Autodesk Fusion 360 part; units mm, degrees
(part 2 of 5)
  arc A33 (14.5583, -1.6533) -> (13.4619, -2.4667) centre (14.4455, -2.6469) ccw
  line L16 (14.5583, -1.6533) -> (14.9391, -1.6965)
  spline S16 degree 5 poles (14.9391, -1.6965) (14.9477, -1.6975) (14.9651, -1.6992) (14.9913, -1.7011) (15.0262, -1.7021) (15.07, -1.7014) (15.1138, -1.6994) (15.1577, -1.6964) (15.2016, -1.693) (15.2456, -1.6893) (15.2896, -1.6852) (15.3336, -1.6807) (15.3777, -1.6756) (15.4217, -1.6698) (15.4658, -1.6634) (15.5099, -1.6563) (15.554, -1.6486) (15.5981, -1.6405) (15.6422, -1.632) (15.6863, -1.6231) (15.7304, -1.6138) (15.7745, -1.6041) (15.8186, -1.594) (15.8627, -1.5835) (15.9068, -1.5726) (15.9508, -1.5612) (15.9949, -1.5494) (16.039, -1.5373) (16.083, -1.5248) (16.127, -1.512) (16.171, -1.4988) (16.215, -1.4852) (16.2589, -1.4713) (16.3029, -1.4571) (16.3468, -1.4425) (16.3907, -1.4276) (16.4345, -1.4123) (16.4784, -1.3967) (16.5222, -1.3808) (16.5659, -1.3646) (16.6097, -1.348) (16.6534, -1.3312) (16.6971, -1.314) (16.7407, -1.2965) (16.7844, -1.2787) (16.8279, -1.2606) (16.8715, -1.2422) (16.915, -1.2235) (16.9585, -1.2045) (17.0019, -1.1853) (17.0453, -1.1657) (17.0886, -1.1458) (17.1319, -1.1257) (17.1752, -1.1053) (17.2184, -1.0846) (17.2616, -1.0636) (17.3047, -1.0423) (17.3478, -1.0208) (17.3908, -0.9989) (17.4338, -0.9769) (17.4767, -0.9545) (17.5196, -0.9319) (17.5624, -0.909) (17.6052, -0.8858) (17.6479, -0.8624) (17.6906, -0.8387) (17.7332, -0.8147) (17.7758, -0.7905) (17.8183, -0.766) (17.8607, -0.7413) (17.9031, -0.7163) (17.937, -0.6962) (17.9623, -0.6809) (17.9792, -0.6707) (17.9877, -0.6655) knots 0 0 0 0 0 0 0.01428571 0.02857143 0.04285714 0.05714286 0.07142857 0.08571429 0.1 0.11428571 0.12857143 0.14285714 0.15714286 0.17142857 0.18571429 0.2 0.21428571 0.22857143 0.24285714 0.25714286 0.27142857 0.28571429 0.3 0.31428571 0.32857143 0.34285714 0.35714286 0.37142857 0.38571429 0.4 0.41428571 0.42857143 0.44285714 0.45714286 0.47142857 0.48571429 0.5 0.51428571 0.52857143 0.54285714 0.55714286 0.57142857 0.58571429 0.6 0.61428571 0.62857143 0.64285714 0.65714286 0.67142857 0.68571429 0.7 0.71428571 0.72857143 0.74285714 0.75714286 0.77142857 0.78571429 0.8 0.81428571 0.82857143 0.84285714 0.85714286 0.87142857 0.88571429 0.9 0.91428571 0.92857143 0.94285714 0.95714286 0.97142857 0.98571429 1 1 1 1 1 1
  arc A34 (17.9877, -0.6655) -> (17.9877, 0.6655) centre (0, 0) ccw
  spline S17 degree 5 poles (17.9877, 0.6655) (17.9792, 0.6707) (17.9623, 0.6809) (17.937, 0.6962) (17.9031, 0.7163) (17.8607, 0.7413) (17.8183, 0.766) (17.7758, 0.7905) (17.7332, 0.8147) (17.6906, 0.8387) (17.6479, 0.8624) (17.6052, 0.8858) (17.5624, 0.909) (17.5196, 0.9319) (17.4767, 0.9545) (17.4338, 0.9769) (17.3908, 0.9989) (17.3478, 1.0208) (17.3047, 1.0423) (17.2616, 1.0636) (17.2184, 1.0846) (17.1752, 1.1053) (17.1319, 1.1257) (17.0886, 1.1458) (17.0453, 1.1657) (17.0019, 1.1853) (16.9585, 1.2045) (16.915, 1.2235) (16.8715, 1.2422) (16.8279, 1.2606) (16.7844, 1.2787) (16.7407, 1.2965) (16.6971, 1.314) (16.6534, 1.3312) (16.6097, 1.348) (16.5659, 1.3646) (16.5222, 1.3808) (16.4784, 1.3967) (16.4345, 1.4123) (16.3907, 1.4276) (16.3468, 1.4425) (16.3029, 1.4571) (16.2589, 1.4713) (16.215, 1.4852) (16.171, 1.4988) (16.127, 1.512) (16.083, 1.5248) (16.039, 1.5373) (15.9949, 1.5494) (15.9508, 1.5612) (15.9068, 1.5726) (15.8627, 1.5835) (15.8186, 1.594) (15.7745, 1.6041) (15.7304, 1.6138) (15.6863, 1.6231) (15.6422, 1.632) (15.5981, 1.6405) (15.554, 1.6486) (15.5099, 1.6563) (15.4658, 1.6634) (15.4217, 1.6698) (15.3777, 1.6756) (15.3336, 1.6807) (15.2896, 1.6852) (15.2456, 1.6893) (15.2016, 1.693) (15.1577, 1.6964) (15.1138, 1.6994) (15.07, 1.7014) (15.0262, 1.7021) (14.9913, 1.7011) (14.9651, 1.6992) (14.9477, 1.6975) (14.9391, 1.6965) knots -1 -1 -1 -1 -1 -1 -0.98571429 -0.97142857 -0.95714286 -0.94285714 -0.92857143 -0.91428571 -0.9 -0.88571429 -0.87142857 -0.85714286 -0.84285714 -0.82857143 -0.81428571 -0.8 -0.78571429 -0.77142857 -0.75714286 -0.74285714 -0.72857143 -0.71428571 -0.7 -0.68571429 -0.67142857 -0.65714286 -0.64285714 -0.62857143 -0.61428571 -0.6 -0.58571429 -0.57142857 -0.55714286 -0.54285714 -0.52857143 -0.51428571 -0.5 -0.48571429 -0.47142857 -0.45714286 -0.44285714 -0.42857143 -0.41428571 -0.4 -0.38571429 -0.37142857 -0.35714286 -0.34285714 -0.32857143 -0.31428571 -0.3 -0.28571429 -0.27142857 -0.25714286 -0.24285714 -0.22857143 -0.21428571 -0.2 -0.18571429 -0.17142857 -0.15714286 -0.14285714 -0.12857143 -0.11428571 -0.1 -0.08571429 -0.07142857 -0.05714286 -0.04285714 -0.02857143 -0.01428571 0 0 0 0 0 0
  line L17 (14.9391, 1.6965) -> (14.5583, 1.6533)
  arc A35 (13.4619, 2.4667) -> (14.5583, 1.6533) centre (14.4455, 2.6469) ccw
  arc A36 (13.4619, 2.4667) -> (13.3811, 2.8727) centre (0, 0) ccw
  arc A37 (14.0828, 4.0438) -> (13.3811, 2.8727) centre (14.3588, 3.0826) ccw
  line L18 (14.0828, 4.0438) -> (14.4511, 4.1495)
  spline S18 degree 5 poles (14.4511, 4.1495) (14.4595, 4.152) (14.4763, 4.157) (14.5011, 4.1653) (14.5338, 4.1777) (14.5739, 4.1951) (14.6136, 4.2138) (14.6531, 4.2333) (14.6924, 4.2533) (14.7316, 4.2735) (14.7707, 4.2941) (14.8096, 4.3152) (14.8483, 4.3367) (14.8868, 4.3589) (14.9251, 4.3818) (14.9631, 4.4052) (15.0009, 4.4291) (15.0385, 4.4535) (15.076, 4.4783) (15.1134, 4.5034) (15.1506, 4.5288) (15.1876, 4.5546) (15.2245, 4.5808) (15.2612, 4.6074) (15.2977, 4.6344) (15.3341, 4.6618) (15.3703, 4.6895) (15.4064, 4.7176) (15.4423, 4.746) (15.478, 4.7747) (15.5136, 4.8037) (15.549, 4.833) (15.5843, 4.8627) (15.6195, 4.8927) (15.6545, 4.9229) (15.6893, 4.9535) (15.724, 4.9844) (15.7585, 5.0156) (15.7929, 5.0471) (15.8271, 5.0788) (15.8612, 5.1108) (15.8952, 5.1432) (15.9289, 5.1757) (15.9626, 5.2086) (15.9961, 5.2417) (16.0294, 5.2751) (16.0626, 5.3088) (16.0956, 5.3427) (16.1285, 5.3769) (16.1613, 5.4113) (16.1939, 5.446) (16.2263, 5.4809) (16.2586, 5.5161) (16.2908, 5.5515) (16.3228, 5.5872) (16.3546, 5.6231) (16.3863, 5.6593) (16.4179, 5.6957) (16.4493, 5.7323) (16.4806, 5.7691) (16.5117, 5.8062) (16.5426, 5.8435) (16.5734, 5.8811) (16.6041, 5.9189) (16.6346, 5.9569) (16.6649, 5.9951) (16.6951, 6.0335) (16.7252, 6.0722) (16.7551, 6.111) (16.7849, 6.1501) (16.8144, 6.1894) (16.838, 6.221) (16.8556, 6.2448) (16.8673, 6.2607) (16.8732, 6.2687) knots 0 0 0 0 0 0 0.01428571 0.02857143 0.04285714 0.05714286 0.07142857 0.08571429 0.1 0.11428571 0.12857143 0.14285714 0.15714286 0.17142857 0.18571429 0.2 0.21428571 0.22857143 0.24285714 0.25714286 0.27142857 0.28571429 0.3 0.31428571 0.32857143 0.34285714 0.35714286 0.37142857 0.38571429 0.4 0.41428571 0.42857143 0.44285714 0.45714286 0.47142857 0.48571429 0.5 0.51428571 0.52857143 0.54285714 0.55714286 0.57142857 0.58571429 0.6 0.61428571 0.62857143 0.64285714 0.65714286 0.67142857 0.68571429 0.7 0.71428571 0.72857143 0.74285714 0.75714286 0.77142857 0.78571429 0.8 0.81428571 0.82857143 0.84285714 0.85714286 0.87142857 0.88571429 0.9 0.91428571 0.92857143 0.94285714 0.95714286 0.97142857 0.98571429 1 1 1 1 1 1
  arc A38 (16.8732, 6.2687) -> (16.3638, 7.4985) centre (0, 0) ccw
  spline S19 degree 5 poles (16.3638, 7.4985) (16.354, 7.5) (16.3345, 7.503) (16.3052, 7.5073) (16.2662, 7.513) (16.2175, 7.5199) (16.1688, 7.5265) (16.1202, 7.5328) (16.0716, 7.5389) (16.023, 7.5447) (15.9746, 7.5503) (15.9261, 7.5556) (15.8777, 7.5606) (15.8294, 7.5654) (15.7811, 7.5699) (15.7329, 7.5741) (15.6847, 7.5781) (15.6366, 7.5818) (15.5886, 7.5852) (15.5406, 7.5883) (15.4927, 7.5912) (15.4448, 7.5938) (15.3971, 7.5961) (15.3493, 7.5982) (15.3017, 7.5999) (15.2541, 7.6014) (15.2066, 7.6026) (15.1592, 7.6035) (15.1118, 7.6041) (15.0646, 7.6044) (15.0174, 7.6045) (14.9703, 7.6042) (14.9233, 7.6037) (14.8763, 7.6028) (14.8295, 7.6017) (14.7827, 7.6002) (14.7361, 7.5984) (14.6895, 7.5964) (14.6431, 7.594) (14.5967, 7.5913) (14.5504, 7.5883) (14.5043, 7.585) (14.4582, 7.5813) (14.4123, 7.5774) (14.3665, 7.573) (14.3208, 7.5684) (14.2752, 7.5634) (14.2298, 7.5581) (14.1844, 7.5525) (14.1392, 7.5465) (14.0942, 7.5401) (14.0492, 7.5334) (14.0045, 7.5262) (13.9599, 7.5187) (13.9154, 7.5107) (13.8711, 7.5024) (13.827, 7.4938) (13.783, 7.4847) (13.7391, 7.4754) (13.6955, 7.4656) (13.652, 7.4552) (13.6088, 7.4444) (13.5659, 7.4328) (13.5232, 7.4207) (13.4809, 7.408) (13.4387, 7.3949) (13.3966, 7.3816) (13.3547, 7.3679) (13.313, 7.3538) (13.2717, 7.3389) (13.231, 7.3228) (13.1992, 7.3085) (13.1757, 7.2968) (13.1603, 7.2886) (13.1527, 7.2843) knots -1 -1 -1 -1 -1 -1 -0.98571429 -0.97142857 -0.95714286 -0.94285714 -0.92857143 -0.91428571 -0.9 -0.88571429 -0.87142857 -0.85714286 -0.84285714 -0.82857143 -0.81428571 -0.8 -0.78571429 -0.77142857 -0.75714286 -0.74285714 -0.72857143 -0.71428571 -0.7 -0.68571429 -0.67142857 -0.65714286 -0.64285714 -0.62857143 -0.61428571 -0.6 -0.58571429 -0.57142857 -0.55714286 -0.54285714 -0.52857143 -0.51428571 -0.5 -0.48571429 -0.47142857 -0.45714286 -0.44285714 -0.42857143 -0.41428571 -0.4 -0.38571429 -0.37142857 -0.35714286 -0.34285714 -0.32857143 -0.31428571 -0.3 -0.28571429 -0.27142857 -0.25714286 -0.24285714 -0.22857143 -0.21428571 -0.2 -0.18571429 -0.17142857 -0.15714286 -0.14285714 -0.12857143 -0.11428571 -0.1 -0.08571429 -0.07142857 -0.05714286 -0.04285714 -0.02857143 -0.01428571 0 0 0 0 0 0
  line L19 (13.1527, 7.2843) -> (12.8175, 7.0987)
  arc A39 (11.4932, 7.4305) -> (12.8175, 7.0987) centre (12.333, 7.9735) ccw
  arc A40 (11.4932, 7.4305) -> (11.2632, 7.7748) centre (0, 0) ccw
  arc A41 (11.4634, 9.1252) -> (11.2632, 7.7748) centre (12.0862, 8.3429) ccw
  line L20 (11.4634, 9.1252) -> (11.7631, 9.3639)
  spline S20 degree 5 poles (11.7631, 9.3639) (11.77, 9.3693) (11.7835, 9.3804) (11.8033, 9.3976) (11.8287, 9.4216) (11.8592, 9.453) (11.8887, 9.4854) (11.9177, 9.5186) (11.9463, 9.552) (11.9748, 9.5858) (12.003, 9.6198) (12.031, 9.6541) (12.0585, 9.6888) (12.0856, 9.7241) (12.1121, 9.7598) (12.1383, 9.796) (12.1641, 9.8326) (12.1895, 9.8695) (12.2147, 9.9067) (12.2396, 9.9442) (12.2642, 9.982) (12.2886, 10.02) (12.3126, 10.0583) (12.3363, 10.0969) (12.3598, 10.1358) (12.3829, 10.175) (12.4057, 10.2145) (12.4283, 10.2542) (12.4506, 10.2942) (12.4726, 10.3344) (12.4944, 10.3748) (12.5159, 10.4155) (12.5372, 10.4564) (12.5582, 10.4975) (12.5789, 10.5389) (12.5994, 10.5805) (12.6196, 10.6223) (12.6396, 10.6643) (12.6593, 10.7066) (12.6788, 10.749) (12.698, 10.7916) (12.717, 10.8345) (12.7358, 10.8775) (12.7543, 10.9207) (12.7725, 10.9642) (12.7905, 11.0078) (12.8083, 11.0516) (12.8259, 11.0955) (12.8432, 11.1397) (12.8603, 11.184) (12.8771, 11.2286) (12.8937, 11.2733) (12.9101, 11.3181) (12.9262, 11.3632) (12.9422, 11.4084) (12.9578, 11.4537) (12.9733, 11.4993) (12.9885, 11.545) (13.0035, 11.5908) (13.0183, 11.6368) (13.0328, 11.683) (13.0472, 11.7293) (13.0613, 11.7758) (13.0751, 11.8224) (13.0888, 11.8692) (13.1022, 11.9161) (13.1154, 11.9632) (13.1284, 12.0104) (13.1411, 12.0578) (13.1536, 12.1052) (13.1659, 12.1529) (13.1756, 12.1911) (13.1828, 12.2198) (13.1875, 12.239) (13.1898, 12.2486) knots 0 0 0 0 0 0 0.01428571 0.02857143 0.04285714 0.05714286 0.07142857 0.08571429 0.1 0.11428571 0.12857143 0.14285714 0.15714286 0.17142857 0.18571429 0.2 0.21428571 0.22857143 0.24285714 0.25714286 0.27142857 0.28571429 0.3 0.31428571 0.32857143 0.34285714 0.35714286 0.37142857 0.38571429 0.4 0.41428571 0.42857143 0.44285714 0.45714286 0.47142857 0.48571429 0.5 0.51428571 0.52857143 0.54285714 0.55714286 0.57142857 0.58571429 0.6 0.61428571 0.62857143 0.64285714 0.65714286 0.67142857 0.68571429 0.7 0.71428571 0.72857143 0.74285714 0.75714286 0.77142857 0.78571429 0.8 0.81428571 0.82857143 0.84285714 0.85714286 0.87142857 0.88571429 0.9 0.91428571 0.92857143 0.94285714 0.95714286 0.97142857 0.98571429 1 1 1 1 1 1
  arc A42 (13.1898, 12.2486) -> (12.2486, 13.1898) centre (0, 0) ccw
  spline S21 degree 5 poles (12.2486, 13.1898) (12.239, 13.1875) (12.2198, 13.1828) (12.1911, 13.1756) (12.1529, 13.1659) (12.1052, 13.1536) (12.0578, 13.1411) (12.0104, 13.1284) (11.9632, 13.1154) (11.9161, 13.1022) (11.8692, 13.0888) (11.8224, 13.0751) (11.7758, 13.0613) (11.7293, 13.0472) (11.683, 13.0328) (11.6368, 13.0183) (11.5908, 13.0035) (11.545, 12.9885) (11.4993, 12.9733) (11.4537, 12.9578) (11.4084, 12.9422) (11.3632, 12.9262) (11.3181, 12.9101) (11.2733, 12.8937) (11.2286, 12.8771) (11.184, 12.8603) (11.1397, 12.8432) (11.0955, 12.8259) (11.0516, 12.8083) (11.0078, 12.7905) (10.9642, 12.7725) (10.9207, 12.7543) (10.8775, 12.7358) (10.8345, 12.717) (10.7916, 12.698) (10.749, 12.6788) (10.7066, 12.6593) (10.6643, 12.6396) (10.6223, 12.6196) (10.5805, 12.5994) (10.5389, 12.5789) (10.4975, 12.5582) (10.4564, 12.5372) (10.4155, 12.5159) (10.3748, 12.4944) (10.3344, 12.4726) (10.2942, 12.4506) (10.2542, 12.4283) (10.2145, 12.4057) (10.175, 12.3829) (10.1358, 12.3598) (10.0969, 12.3363) (10.0583, 12.3126) (10.02, 12.2886) (9.982, 12.2642) (9.9442, 12.2396) (9.9067, 12.2147) (9.8695, 12.1895) (9.8326, 12.1641) (9.796, 12.1383) (9.7598, 12.1121) (9.7241, 12.0856) (9.6888, 12.0585) (9.6541, 12.031) (9.6198, 12.003) (9.5858, 11.9748) (9.552, 11.9463) (9.5186, 11.9177) (9.4854, 11.8887) (9.453, 11.8592) (9.4216, 11.8287) (9.3976, 11.8033) (9.3804, 11.7835) (9.3693, 11.77) (9.3639, 11.7631) knots -1 -1 -1 -1 -1 -1 -0.98571429 -0.97142857 -0.95714286 -0.94285714 -0.92857143 -0.91428571 -0.9 -0.88571429 -0.87142857 -0.85714286 -0.84285714 -0.82857143 -0.81428571 -0.8 -0.78571429 -0.77142857 -0.75714286 -0.74285714 -0.72857143 -0.71428571 -0.7 -0.68571429 -0.67142857 -0.65714286 -0.64285714 -0.62857143 -0.61428571 -0.6 -0.58571429 -0.57142857 -0.55714286 -0.54285714 -0.52857143 -0.51428571 -0.5 -0.48571429 -0.47142857 -0.45714286 -0.44285714 -0.42857143 -0.41428571 -0.4 -0.38571429 -0.37142857 -0.35714286 -0.34285714 -0.32857143 -0.31428571 -0.3 -0.28571429 -0.27142857 -0.25714286 -0.24285714 -0.22857143 -0.21428571 -0.2 -0.18571429 -0.17142857 -0.15714286 -0.14285714 -0.12857143 -0.11428571 -0.1 -0.08571429 -0.07142857 -0.05714286 -0.04285714 -0.02857143 -0.01428571 0 0 0 0 0 0
  line L21 (9.3639, 11.7631) -> (9.1252, 11.4634)
  arc A43 (7.7748, 11.2632) -> (9.1252, 11.4634) centre (8.3429, 12.0862) ccw
  arc A44 (7.7748, 11.2632) -> (7.4305, 11.4932) centre (0, 0) ccw
  arc A45 (7.0987, 12.8175) -> (7.4305, 11.4932) centre (7.9735, 12.333) ccw
  line L22 (7.0987, 12.8175) -> (7.2843, 13.1527)
  spline S22 degree 5 poles (7.2843, 13.1527) (7.2886, 13.1603) (7.2968, 13.1757) (7.3085, 13.1992) (7.3228, 13.231) (7.3389, 13.2717) (7.3538, 13.313) (7.3679, 13.3547) (7.3816, 13.3966) (7.3949, 13.4387) (7.408, 13.4809) (7.4207, 13.5232) (7.4328, 13.5659) (7.4444, 13.6088) (7.4552, 13.652) (7.4656, 13.6955) (7.4754, 13.7391) (7.4847, 13.783) (7.4938, 13.827) (7.5024, 13.8711) (7.5107, 13.9154) (7.5187, 13.9599) (7.5262, 14.0045) (7.5334, 14.0492) (7.5401, 14.0942) (7.5465, 14.1392) (7.5525, 14.1844) (7.5581, 14.2298) (7.5634, 14.2752) (7.5684, 14.3208) (7.573, 14.3665) (7.5774, 14.4123) (7.5813, 14.4582) (7.585, 14.5043) (7.5883, 14.5504) (7.5913, 14.5967) (7.594, 14.6431) (7.5964, 14.6895) (7.5984, 14.7361) (7.6002, 14.7827) (7.6017, 14.8295) (7.6028, 14.8763) (7.6037, 14.9233) (7.6042, 14.9703) (7.6045, 15.0174) (7.6044, 15.0646) (7.6041, 15.1118) (7.6035, 15.1592) (7.6026, 15.2066) (7.6014, 15.2541) (7.5999, 15.3017) (7.5982, 15.3493) (7.5961, 15.3971) (7.5938, 15.4448) (7.5912, 15.4927) (7.5883, 15.5406) (7.5852, 15.5886) (7.5818, 15.6366) (7.5781, 15.6847) (7.5741, 15.7329) (7.5699, 15.7811) (7.5654, 15.8294) (7.5606, 15.8777) (7.5556, 15.9261) (7.5503, 15.9746) (7.5447, 16.023) (7.5389, 16.0716) (7.5328, 16.1202) (7.5265, 16.1688) (7.5199, 16.2175) (7.513, 16.2662) (7.5073, 16.3052) (7.503, 16.3345) (7.5, 16.354) (7.4985, 16.3638) knots 0 0 0 0 0 0 0.01428571 0.02857143 0.04285714 0.05714286 0.07142857 0.08571429 0.1 0.11428571 0.12857143 0.14285714 0.15714286 0.17142857 0.18571429 0.2 0.21428571 0.22857143 0.24285714 0.25714286 0.27142857 0.28571429 0.3 0.31428571 0.32857143 0.34285714 0.35714286 0.37142857 0.38571429 0.4 0.41428571 0.42857143 0.44285714 0.45714286 0.47142857 0.48571429 0.5 0.51428571 0.52857143 0.54285714 0.55714286 0.57142857 0.58571429 0.6 0.61428571 0.62857143 0.64285714 0.65714286 0.67142857 0.68571429 0.7 0.71428571 0.72857143 0.74285714 0.75714286 0.77142857 0.78571429 0.8 0.81428571 0.82857143 0.84285714 0.85714286 0.87142857 0.88571429 0.9 0.91428571 0.92857143 0.94285714 0.95714286 0.97142857 0.98571429 1 1 1 1 1 1
  arc A46 (7.4985, 16.3638) -> (6.2687, 16.8732) centre (0, 0) ccw
  spline S23 degree 5 poles (6.2687, 16.8732) (6.2607, 16.8673) (6.2448, 16.8556) (6.221, 16.838) (6.1894, 16.8144) (6.1501, 16.7849) (6.111, 16.7551) (6.0722, 16.7252) (6.0335, 16.6951) (5.9951, 16.6649) (5.9569, 16.6346) (5.9189, 16.6041) (5.8811, 16.5734) (5.8435, 16.5426) (5.8062, 16.5117) (5.7691, 16.4806) (5.7323, 16.4493) (5.6957, 16.4179) (5.6593, 16.3863) (5.6231, 16.3546) (5.5872, 16.3228) (5.5515, 16.2908) (5.5161, 16.2586) (5.4809, 16.2263) (5.446, 16.1939) (5.4113, 16.1613) (5.3769, 16.1285) (5.3427, 16.0956) (5.3088, 16.0626) (5.2751, 16.0294) (5.2417, 15.9961) (5.2086, 15.9626) (5.1757, 15.9289) (5.1432, 15.8952) (5.1108, 15.8612) (5.0788, 15.8271) (5.0471, 15.7929) (5.0156, 15.7585) (4.9844, 15.724) (4.9535, 15.6893) (4.9229, 15.6545) (4.8927, 15.6195) (4.8627, 15.5843) (4.833, 15.549) (4.8037, 15.5136) (4.7747, 15.478) (4.746, 15.4423) (4.7176, 15.4064) (4.6895, 15.3703) (4.6618, 15.3341) (4.6344, 15.2977) (4.6074, 15.2612) (4.5808, 15.2245) (4.5546, 15.1876) (4.5288, 15.1506) (4.5034, 15.1134) (4.4783, 15.076) (4.4535, 15.0385) (4.4291, 15.0009) (4.4052, 14.9631) (4.3818, 14.9251) (4.3589, 14.8868) (4.3367, 14.8483) (4.3152, 14.8096) (4.2941, 14.7707) (4.2735, 14.7316) (4.2533, 14.6924) (4.2333, 14.6531) (4.2138, 14.6136) (4.1951, 14.5739) (4.1777, 14.5338) (4.1653, 14.5011) (4.157, 14.4763) (4.152, 14.4595) (4.1495, 14.4511) knots -1 -1 -1 -1 -1 -1 -0.98571429 -0.97142857 -0.95714286 -0.94285714 -0.92857143 -0.91428571 -0.9 -0.88571429 -0.87142857 -0.85714286 -0.84285714 -0.82857143 -0.81428571 -0.8 -0.78571429 -0.77142857 -0.75714286 -0.74285714 -0.72857143 -0.71428571 -0.7 -0.68571429 -0.67142857 -0.65714286 -0.64285714 -0.62857143 -0.61428571 -0.6 -0.58571429 -0.57142857 -0.55714286 -0.54285714 -0.52857143 -0.51428571 -0.5 -0.48571429 -0.47142857 -0.45714286 -0.44285714 -0.42857143 -0.41428571 -0.4 -0.38571429 -0.37142857 -0.35714286 -0.34285714 -0.32857143 -0.31428571 -0.3 -0.28571429 -0.27142857 -0.25714286 -0.24285714 -0.22857143 -0.21428571 -0.2 -0.18571429 -0.17142857 -0.15714286 -0.14285714 -0.12857143 -0.11428571 -0.1 -0.08571429 -0.07142857 -0.05714286 -0.04285714 -0.02857143 -0.01428571 0 0 0 0 0 0
  line L23 (4.1495, 14.4511) -> (4.0438, 14.0828)
  arc A47 (2.8727, 13.3811) -> (4.0438, 14.0828) centre (3.0826, 14.3588) ccw
  arc A48 (2.8727, 13.3811) -> (2.4667, 13.4619) centre (0, 0) ccw
  arc A49 (1.6533, 14.5583) -> (2.4667, 13.4619) centre (2.6469, 14.4455) ccw
  line L24 (1.6533, 14.5583) -> (1.6965, 14.9391)
  spline S24 degree 5 poles (1.6965, 14.9391) (1.6975, 14.9477) (1.6992, 14.9651) (1.7011, 14.9913) (1.7021, 15.0262) (1.7014, 15.07) (1.6994, 15.1138) (1.6964, 15.1577) (1.693, 15.2016) (1.6893, 15.2456) (1.6852, 15.2896) (1.6807, 15.3336) (1.6756, 15.3777) (1.6698, 15.4217) (1.6634, 15.4658) (1.6563, 15.5099) (1.6486, 15.554) (1.6405, 15.5981) (1.632, 15.6422) (1.6231, 15.6863) (1.6138, 15.7304) (1.6041, 15.7745) (1.594, 15.8186) (1.5835, 15.8627) (1.5726, 15.9068) (1.5612, 15.9508) (1.5494, 15.9949) (1.5373, 16.039) (1.5248, 16.083) (1.512, 16.127) (1.4988, 16.171) (1.4852, 16.215) (1.4713, 16.2589) (1.4571, 16.3029) (1.4425, 16.3468) (1.4276, 16.3907) (1.4123, 16.4345) (1.3967, 16.4784) (1.3808, 16.5222) (1.3646, 16.5659) (1.348, 16.6097) (1.3312, 16.6534) (1.314, 16.6971) (1.2965, 16.7407) (1.2787, 16.7844) (1.2606, 16.8279) (1.2422, 16.8715) (1.2235, 16.915) (1.2045, 16.9585) (1.1853, 17.0019) (1.1657, 17.0453) (1.1458, 17.0886) (1.1257, 17.1319) (1.1053, 17.1752) (1.0846, 17.2184) (1.0636, 17.2616) (1.0423, 17.3047) (1.0208, 17.3478) (0.9989, 17.3908) (0.9769, 17.4338) (0.9545, 17.4767) (0.9319, 17.5196) (0.909, 17.5624) (0.8858, 17.6052) (0.8624, 17.6479) (0.8387, 17.6906) (0.8147, 17.7332) (0.7905, 17.7758) (0.766, 17.8183) (0.7413, 17.8607) (0.7163, 17.9031) (0.6962, 17.937) (0.6809, 17.9623) (0.6707, 17.9792) (0.6655, 17.9877) knots 0 0 0 0 0 0 0.01428571 0.02857143 0.04285714 0.05714286 0.07142857 0.08571429 0.1 0.11428571 0.12857143 0.14285714 0.15714286 0.17142857 0.18571429 0.2 0.21428571 0.22857143 0.24285714 0.25714286 0.27142857 0.28571429 0.3 0.31428571 0.32857143 0.34285714 0.35714286 0.37142857 0.38571429 0.4 0.41428571 0.42857143 0.44285714 0.45714286 0.47142857 0.48571429 0.5 0.51428571 0.52857143 0.54285714 0.55714286 0.57142857 0.58571429 0.6 0.61428571 0.62857143 0.64285714 0.65714286 0.67142857 0.68571429 0.7 0.71428571 0.72857143 0.74285714 0.75714286 0.77142857 0.78571429 0.8 0.81428571 0.82857143 0.84285714 0.85714286 0.87142857 0.88571429 0.9 0.91428571 0.92857143 0.94285714 0.95714286 0.97142857 0.98571429 1 1 1 1 1 1
  arc A50 (0.6655, 17.9877) -> (-0.6655, 17.9877) centre (0, 0) ccw
  spline S25 degree 5 poles (-0.6655, 17.9877) (-0.6707, 17.9792) (-0.6809, 17.9623) (-0.6962, 17.937) (-0.7163, 17.9031) (-0.7413, 17.8607) (-0.766, 17.8183) (-0.7905, 17.7758) (-0.8147, 17.7332) (-0.8387, 17.6906) (-0.8624, 17.6479) (-0.8858, 17.6052) (-0.909, 17.5624) (-0.9319, 17.5196) (-0.9545, 17.4767) (-0.9769, 17.4338) (-0.9989, 17.3908) (-1.0208, 17.3478) (-1.0423, 17.3047) (-1.0636, 17.2616) (-1.0846, 17.2184) (-1.1053, 17.1752) (-1.1257, 17.1319) (-1.1458, 17.0886) (-1.1657, 17.0453) (-1.1853, 17.0019) (-1.2045, 16.9585) (-1.2235, 16.915) (-1.2422, 16.8715) (-1.2606, 16.8279) (-1.2787, 16.7844) (-1.2965, 16.7407) (-1.314, 16.6971) (-1.3312, 16.6534) (-1.348, 16.6097) (-1.3646, 16.5659) (-1.3808, 16.5222) (-1.3967, 16.4784) (-1.4123, 16.4345) (-1.4276, 16.3907) (-1.4425, 16.3468) (-1.4571, 16.3029) (-1.4713, 16.2589) (-1.4852, 16.215) (-1.4988, 16.171) (-1.512, 16.127) (-1.5248, 16.083) (-1.5373, 16.039) (-1.5494, 15.9949) (-1.5612, 15.9508) (-1.5726, 15.9068) (-1.5835, 15.8627) (-1.594, 15.8186) (-1.6041, 15.7745) (-1.6138, 15.7304) (-1.6231, 15.6863) (-1.632, 15.6422) (-1.6405, 15.5981) (-1.6486, 15.554) (-1.6563, 15.5099) (-1.6634, 15.4658) (-1.6698, 15.4217) (-1.6756, 15.3777) (-1.6807, 15.3336) (-1.6852, 15.2896) (-1.6893, 15.2456) (-1.693, 15.2016) (-1.6964, 15.1577) (-1.6994, 15.1138) (-1.7014, 15.07) (-1.7021, 15.0262) (-1.7011, 14.9913) (-1.6992, 14.9651) (-1.6975, 14.9477) (-1.6965, 14.9391) knots -1 -1 -1 -1 -1 -1 -0.98571429 -0.97142857 -0.95714286 -0.94285714 -0.92857143 -0.91428571 -0.9 -0.88571429 -0.87142857 -0.85714286 -0.84285714 -0.82857143 -0.81428571 -0.8 -0.78571429 -0.77142857 -0.75714286 -0.74285714 -0.72857143 -0.71428571 -0.7 -0.68571429 -0.67142857 -0.65714286 -0.64285714 -0.62857143 -0.61428571 -0.6 -0.58571429 -0.57142857 -0.55714286 -0.54285714 -0.52857143 -0.51428571 -0.5 -0.48571429 -0.47142857 -0.45714286 -0.44285714 -0.42857143 -0.41428571 -0.4 -0.38571429 -0.37142857 -0.35714286 -0.34285714 -0.32857143 -0.31428571 -0.3 -0.28571429 -0.27142857 -0.25714286 -0.24285714 -0.22857143 -0.21428571 -0.2 -0.18571429 -0.17142857 -0.15714286 -0.14285714 -0.12857143 -0.11428571 -0.1 -0.08571429 -0.07142857 -0.05714286 -0.04285714 -0.02857143 -0.01428571 0 0 0 0 0 0
  line L25 (-1.6965, 14.9391) -> (-1.6533, 14.5583)
  arc A51 (-2.4667, 13.4619) -> (-1.6533, 14.5583) centre (-2.6469, 14.4455) ccw
  arc A52 (-2.4667, 13.4619) -> (-2.8727, 13.3811) centre (0, 0) ccw
  arc A53 (-4.0438, 14.0828) -> (-2.8727, 13.3811) centre (-3.0826, 14.3588) ccw
  line L26 (-4.0438, 14.0828) -> (-4.1495, 14.4511)
  spline S26 degree 5 poles (-4.1495, 14.4511) (-4.152, 14.4595) (-4.157, 14.4763) (-4.1653, 14.5011) (-4.1777, 14.5338) (-4.1951, 14.5739) (-4.2138, 14.6136) (-4.2333, 14.6531) (-4.2533, 14.6924) (-4.2735, 14.7316) (-4.2941, 14.7707) (-4.3152, 14.8096) (-4.3367, 14.8483) (-4.3589, 14.8868) (-4.3818, 14.9251) (-4.4052, 14.9631) (-4.4291, 15.0009) (-4.4535, 15.0385) (-4.4783, 15.076) (-4.5034, 15.1134) (-4.5288, 15.1506) (-4.5546, 15.1876) (-4.5808, 15.2245) (-4.6074, 15.2612) (-4.6344, 15.2977) (-4.6618, 15.3341) (-4.6895, 15.3703) (-4.7176, 15.4064) (-4.746, 15.4423) (-4.7747, 15.478) (-4.8037, 15.5136) (-4.833, 15.549) (-4.8627, 15.5843) (-4.8927, 15.6195) (-4.9229, 15.6545) (-4.9535, 15.6893) (-4.9844, 15.724) (-5.0156, 15.7585) (-5.0471, 15.7929) (-5.0788, 15.8271) (-5.1108, 15.8612) (-5.1432, 15.8952) (-5.1757, 15.9289) (-5.2086, 15.9626) (-5.2417, 15.9961) (-5.2751, 16.0294) (-5.3088, 16.0626) (-5.3427, 16.0956) (-5.3769, 16.1285) (-5.4113, 16.1613) (-5.446, 16.1939) (-5.4809, 16.2263) (-5.5161, 16.2586) (-5.5515, 16.2908) (-5.5872, 16.3228) (-5.6231, 16.3546) (-5.6593, 16.3863) (-5.6957, 16.4179) (-5.7323, 16.4493) (-5.7691, 16.4806) (-5.8062, 16.5117) (-5.8435, 16.5426) (-5.8811, 16.5734) (-5.9189, 16.6041) (-5.9569, 16.6346) (-5.9951, 16.6649) (-6.0335, 16.6951) (-6.0722, 16.7252) (-6.111, 16.7551) (-6.1501, 16.7849) (-6.1894, 16.8144) (-6.221, 16.838) (-6.2448, 16.8556) (-6.2607, 16.8673) (-6.2687, 16.8732) knots 0 0 0 0 0 0 0.01428571 0.02857143 0.04285714 0.05714286 0.07142857 0.08571429 0.1 0.11428571 0.12857143 0.14285714 0.15714286 0.17142857 0.18571429 0.2 0.21428571 0.22857143 0.24285714 0.25714286 0.27142857 0.28571429 0.3 0.31428571 0.32857143 0.34285714 0.35714286 0.37142857 0.38571429 0.4 0.41428571 0.42857143 0.44285714 0.45714286 0.47142857 0.48571429 0.5 0.51428571 0.52857143 0.54285714 0.55714286 0.57142857 0.58571429 0.6 0.61428571 0.62857143 0.64285714 0.65714286 0.67142857 0.68571429 0.7 0.71428571 0.72857143 0.74285714 0.75714286 0.77142857 0.78571429 0.8 0.81428571 0.82857143 0.84285714 0.85714286 0.87142857 0.88571429 0.9 0.91428571 0.92857143 0.94285714 0.95714286 0.97142857 0.98571429 1 1 1 1 1 1
  arc A54 (-6.2687, 16.8732) -> (-7.4985, 16.3638) centre (0, 0) ccw
  spline S27 degree 5 poles (-7.4985, 16.3638) (-7.5, 16.354) (-7.503, 16.3345) (-7.5073, 16.3052) (-7.513, 16.2662) (-7.5199, 16.2175) (-7.5265, 16.1688) (-7.5328, 16.1202) (-7.5389, 16.0716) (-7.5447, 16.023) (-7.5503, 15.9746) (-7.5556, 15.9261) (-7.5606, 15.8777) (-7.5654, 15.8294) (-7.5699, 15.7811) (-7.5741, 15.7329) (-7.5781, 15.6847) (-7.5818, 15.6366) (-7.5852, 15.5886) (-7.5883, 15.5406) (-7.5912, 15.4927) (-7.5938, 15.4448) (-7.5961, 15.3971) (-7.5982, 15.3493) (-7.5999, 15.3017) (-7.6014, 15.2541) (-7.6026, 15.2066) (-7.6035, 15.1592) (-7.6041, 15.1118) (-7.6044, 15.0646) (-7.6045, 15.0174) (-7.6042, 14.9703) (-7.6037, 14.9233) (-7.6028, 14.8763) (-7.6017, 14.8295) (-7.6002, 14.7827) (-7.5984, 14.7361) (-7.5964, 14.6895) (-7.594, 14.6431) (-7.5913, 14.5967) (-7.5883, 14.5504) (-7.585, 14.5043) (-7.5813, 14.4582) (-7.5774, 14.4123) (-7.573, 14.3665) (-7.5684, 14.3208) (-7.5634, 14.2752) (-7.5581, 14.2298) (-7.5525, 14.1844) (-7.5465, 14.1392) (-7.5401, 14.0942) (-7.5334, 14.0492) (-7.5262, 14.0045) (-7.5187, 13.9599) (-7.5107, 13.9154) (-7.5024, 13.8711) (-7.4938, 13.827) (-7.4847, 13.783) (-7.4754, 13.7391) (-7.4656, 13.6955) (-7.4552, 13.652) (-7.4444, 13.6088) (-7.4328, 13.5659) (-7.4207, 13.5232) (-7.408, 13.4809) (-7.3949, 13.4387) (-7.3816, 13.3966) (-7.3679, 13.3547) (-7.3538, 13.313) (-7.3389, 13.2717) (-7.3228, 13.231) (-7.3085, 13.1992) (-7.2968, 13.1757) (-7.2886, 13.1603) (-7.2843, 13.1527) knots -1 -1 -1 -1 -1 -1 -0.98571429 -0.97142857 -0.95714286 -0.94285714 -0.92857143 -0.91428571 -0.9 -0.88571429 -0.87142857 -0.85714286 -0.84285714 -0.82857143 -0.81428571 -0.8 -0.78571429 -0.77142857 -0.75714286 -0.74285714 -0.72857143 -0.71428571 -0.7 -0.68571429 -0.67142857 -0.65714286 -0.64285714 -0.62857143 -0.61428571 -0.6 -0.58571429 -0.57142857 -0.55714286 -0.54285714 -0.52857143 -0.51428571 -0.5 -0.48571429 -0.47142857 -0.45714286 -0.44285714 -0.42857143 -0.41428571 -0.4 -0.38571429 -0.37142857 -0.35714286 -0.34285714 -0.32857143 -0.31428571 -0.3 -0.28571429 -0.27142857 -0.25714286 -0.24285714 -0.22857143 -0.21428571 -0.2 -0.18571429 -0.17142857 -0.15714286 -0.14285714 -0.12857143 -0.11428571 -0.1 -0.08571429 -0.07142857 -0.05714286 -0.04285714 -0.02857143 -0.01428571 0 0 0 0 0 0
  line L27 (-7.2843, 13.1527) -> (-7.0987, 12.8175)
  arc A55 (-7.4305, 11.4932) -> (-7.0987, 12.8175) centre (-7.9735, 12.333) ccw
  arc A56 (-7.4305, 11.4932) -> (-7.7748, 11.2632) centre (0, 0) ccw
  arc A57 (-9.1252, 11.4634) -> (-7.7748, 11.2632) centre (-8.3429, 12.0862) ccw
  line L28 (-9.1252, 11.4634) -> (-9.3639, 11.7631)
  spline S28 degree 5 poles (-9.3639, 11.7631) (-9.3693, 11.77) (-9.3804, 11.7835) (-9.3976, 11.8033) (-9.4216, 11.8287) (-9.453, 11.8592) (-9.4854, 11.8887) (-9.5186, 11.9177) (-9.552, 11.9463) (-9.5858, 11.9748) (-9.6198, 12.003) (-9.6541, 12.031) (-9.6888, 12.0585) (-9.7241, 12.0856) (-9.7598, 12.1121) (-9.796, 12.1383) (-9.8326, 12.1641) (-9.8695, 12.1895) (-9.9067, 12.2147) (-9.9442, 12.2396) (-9.982, 12.2642) (-10.02, 12.2886) (-10.0583, 12.3126) (-10.0969, 12.3363) (-10.1358, 12.3598) (-10.175, 12.3829) (-10.2145, 12.4057) (-10.2542, 12.4283) (-10.2942, 12.4506) (-10.3344, 12.4726) (-10.3748, 12.4944) (-10.4155, 12.5159) (-10.4564, 12.5372) (-10.4975, 12.5582) (-10.5389, 12.5789) (-10.5805, 12.5994) (-10.6223, 12.6196) (-10.6643, 12.6396) (-10.7066, 12.6593) (-10.749, 12.6788) (-10.7916, 12.698) (-10.8345, 12.717) (-10.8775, 12.7358) (-10.9207, 12.7543) (-10.9642, 12.7725) (-11.0078, 12.7905) (-11.0516, 12.8083) (-11.0955, 12.8259) (-11.1397, 12.8432) (-11.184, 12.8603) (-11.2286, 12.8771) (-11.2733, 12.8937) (-11.3181, 12.9101) (-11.3632, 12.9262) (-11.4084, 12.9422) (-11.4537, 12.9578) (-11.4993, 12.9733) (-11.545, 12.9885) (-11.5908, 13.0035) (-11.6368, 13.0183) (-11.683, 13.0328) (-11.7293, 13.0472) (-11.7758, 13.0613) (-11.8224, 13.0751) (-11.8692, 13.0888) (-11.9161, 13.1022) (-11.9632, 13.1154) (-12.0104, 13.1284) (-12.0578, 13.1411) (-12.1052, 13.1536) (-12.1529, 13.1659) (-12.1911, 13.1756) (-12.2198, 13.1828) (-12.239, 13.1875) (-12.2486, 13.1898) knots 0 0 0 0 0 0 0.01428571 0.02857143 0.04285714 0.05714286 0.07142857 0.08571429 0.1 0.11428571 0.12857143 0.14285714 0.15714286 0.17142857 0.18571429 0.2 0.21428571 0.22857143 0.24285714 0.25714286 0.27142857 0.28571429 0.3 0.31428571 0.32857143 0.34285714 0.35714286 0.37142857 0.38571429 0.4 0.41428571 0.42857143 0.44285714 0.45714286 0.47142857 0.48571429 0.5 0.51428571 0.52857143 0.54285714 0.55714286 0.57142857 0.58571429 0.6 0.61428571 0.62857143 0.64285714 0.65714286 0.67142857 0.68571429 0.7 0.71428571 0.72857143 0.74285714 0.75714286 0.77142857 0.78571429 0.8 0.81428571 0.82857143 0.84285714 0.85714286 0.87142857 0.88571429 0.9 0.91428571 0.92857143 0.94285714 0.95714286 0.97142857 0.98571429 1 1 1 1 1 1
  arc A58 (-12.2486, 13.1898) -> (-13.1898, 12.2486) centre (0, 0) ccw
  spline S29 degree 5 poles (-13.1898, 12.2486) (-13.1875, 12.239) (-13.1828, 12.2198) (-13.1756, 12.1911) (-13.1659, 12.1529) (-13.1536, 12.1052) (-13.1411, 12.0578) (-13.1284, 12.0104) (-13.1154, 11.9632) (-13.1022, 11.9161) (-13.0888, 11.8692) (-13.0751, 11.8224) (-13.0613, 11.7758) (-13.0472, 11.7293) (-13.0328, 11.683) (-13.0183, 11.6368) (-13.0035, 11.5908) (-12.9885, 11.545) (-12.9733, 11.4993) (-12.9578, 11.4537) (-12.9422, 11.4084) (-12.9262, 11.3632) (-12.9101, 11.3181) (-12.8937, 11.2733) (-12.8771, 11.2286) (-12.8603, 11.184) (-12.8432, 11.1397) (-12.8259, 11.0955) (-12.8083, 11.0516) (-12.7905, 11.0078) (-12.7725, 10.9642) (-12.7543, 10.9207) (-12.7358, 10.8775) (-12.717, 10.8345) (-12.698, 10.7916) (-12.6788, 10.749) (-12.6593, 10.7066) (-12.6396, 10.6643) (-12.6196, 10.6223) (-12.5994, 10.5805) (-12.5789, 10.5389) (-12.5582, 10.4975) (-12.5372, 10.4564) (-12.5159, 10.4155) (-12.4944, 10.3748) (-12.4726, 10.3344) (-12.4506, 10.2942) (-12.4283, 10.2542) (-12.4057, 10.2145) (-12.3829, 10.175) (-12.3598, 10.1358) (-12.3363, 10.0969) (-12.3126, 10.0583) (-12.2886, 10.02) (-12.2642, 9.982) (-12.2396, 9.9442) (-12.2147, 9.9067) (-12.1895, 9.8695) (-12.1641, 9.8326) (-12.1383, 9.796) (-12.1121, 9.7598) (-12.0856, 9.7241) (-12.0585, 9.6888) (-12.031, 9.6541) (-12.003, 9.6198) (-11.9748, 9.5858) (-11.9463, 9.552) (-11.9177, 9.5186) (-11.8887, 9.4854) (-11.8592, 9.453) (-11.8287, 9.4216) (-11.8033, 9.3976) (-11.7835, 9.3804) (-11.77, 9.3693) (-11.7631, 9.3639) knots -1 -1 -1 -1 -1 -1 -0.98571429 -0.97142857 -0.95714286 -0.94285714 -0.92857143 -0.91428571 -0.9 -0.88571429 -0.87142857 -0.85714286 -0.84285714 -0.82857143 -0.81428571 -0.8 -0.78571429 -0.77142857 -0.75714286 -0.74285714 -0.72857143 -0.71428571 -0.7 -0.68571429 -0.67142857 -0.65714286 -0.64285714 -0.62857143 -0.61428571 -0.6 -0.58571429 -0.57142857 -0.55714286 -0.54285714 -0.52857143 -0.51428571 -0.5 -0.48571429 -0.47142857 -0.45714286 -0.44285714 -0.42857143 -0.41428571 -0.4 -0.38571429 -0.37142857 -0.35714286 -0.34285714 -0.32857143 -0.31428571 -0.3 -0.28571429 -0.27142857 -0.25714286 -0.24285714 -0.22857143 -0.21428571 -0.2 -0.18571429 -0.17142857 -0.15714286 -0.14285714 -0.12857143 -0.11428571 -0.1 -0.08571429 -0.07142857 -0.05714286 -0.04285714 -0.02857143 -0.01428571 0 0 0 0 0 0
  line L29 (-11.7631, 9.3639) -> (-11.4634, 9.1252)
  arc A59 (-11.2632, 7.7748) -> (-11.4634, 9.1252) centre (-12.0862, 8.3429) ccw
  arc A60 (-11.2632, 7.7748) -> (-11.4932, 7.4305) centre (0, 0) ccw
  arc A61 (-12.8175, 7.0987) -> (-11.4932, 7.4305) centre (-12.333, 7.9735) ccw
  line L30 (-12.8175, 7.0987) -> (-13.1527, 7.2843)
  spline S30 degree 5 poles (-13.1527, 7.2843) (-13.1603, 7.2886) (-13.1757, 7.2968) (-13.1992, 7.3085) (-13.231, 7.3228) (-13.2717, 7.3389) (-13.313, 7.3538) (-13.3547, 7.3679) (-13.3966, 7.3816) (-13.4387, 7.3949) (-13.4809, 7.408) (-13.5232, 7.4207) (-13.5659, 7.4328) (-13.6088, 7.4444) (-13.652, 7.4552) (-13.6955, 7.4656) (-13.7391, 7.4754) (-13.783, 7.4847) (-13.827, 7.4938) (-13.8711, 7.5024) (-13.9154, 7.5107) (-13.9599, 7.5187) (-14.0045, 7.5262) (-14.0492, 7.5334) (-14.0942, 7.5401) (-14.1392, 7.5465) (-14.1844, 7.5525) (-14.2298, 7.5581) (-14.2752, 7.5634) (-14.3208, 7.5684) (-14.3665, 7.573) (-14.4123, 7.5774) (-14.4582, 7.5813) (-14.5043, 7.585) (-14.5504, 7.5883) (-14.5967, 7.5913) (-14.6431, 7.594) (-14.6895, 7.5964) (-14.7361, 7.5984) (-14.7827, 7.6002) (-14.8295, 7.6017) (-14.8763, 7.6028) (-14.9233, 7.6037) (-14.9703, 7.6042) (-15.0174, 7.6045) (-15.0646, 7.6044) (-15.1118, 7.6041) (-15.1592, 7.6035) (-15.2066, 7.6026) (-15.2541, 7.6014) (-15.3017, 7.5999) (-15.3493, 7.5982) (-15.3971, 7.5961) (-15.4448, 7.5938) (-15.4927, 7.5912) (-15.5406, 7.5883) (-15.5886, 7.5852) (-15.6366, 7.5818) (-15.6847, 7.5781) (-15.7329, 7.5741) (-15.7811, 7.5699) (-15.8294, 7.5654) (-15.8777, 7.5606) (-15.9261, 7.5556) (-15.9746, 7.5503) (-16.023, 7.5447) (-16.0716, 7.5389) (-16.1202, 7.5328) (-16.1688, 7.5265) (-16.2175, 7.5199) (-16.2662, 7.513) (-16.3052, 7.5073) (-16.3345, 7.503) (-16.354, 7.5) (-16.3638, 7.4985) knots 0 0 0 0 0 0 0.01428571 0.02857143 0.04285714 0.05714286 0.07142857 0.08571429 0.1 0.11428571 0.12857143 0.14285714 0.15714286 0.17142857 0.18571429 0.2 0.21428571 0.22857143 0.24285714 0.25714286 0.27142857 0.28571429 0.3 0.31428571 0.32857143 0.34285714 0.35714286 0.37142857 0.38571429 0.4 0.41428571 0.42857143 0.44285714 0.45714286 0.47142857 0.48571429 0.5 0.51428571 0.52857143 0.54285714 0.55714286 0.57142857 0.58571429 0.6 0.61428571 0.62857143 0.64285714 0.65714286 0.67142857 0.68571429 0.7 0.71428571 0.72857143 0.74285714 0.75714286 0.77142857 0.78571429 0.8 0.81428571 0.82857143 0.84285714 0.85714286 0.87142857 0.88571429 0.9 0.91428571 0.92857143 0.94285714 0.95714286 0.97142857 0.98571429 1 1 1 1 1 1
  arc A62 (-16.3638, 7.4985) -> (-16.8732, 6.2687) centre (0, 0) ccw
  spline S31 degree 5 poles (-16.8732, 6.2687) (-16.8673, 6.2607) (-16.8556, 6.2448) (-16.838, 6.221) (-16.8144, 6.1894) (-16.7849, 6.1501) (-16.7551, 6.111) (-16.7252, 6.0722) (-16.6951, 6.0335) (-16.6649, 5.9951) (-16.6346, 5.9569) (-16.6041, 5.9189) (-16.5734, 5.8811) (-16.5426, 5.8435) (-16.5117, 5.8062) (-16.4806, 5.7691) (-16.4493, 5.7323) (-16.4179, 5.6957) (-16.3863, 5.6593) (-16.3546, 5.6231) (-16.3228, 5.5872) (-16.2908, 5.5515) (-16.2586, 5.5161) (-16.2263, 5.4809) (-16.1939, 5.446) (-16.1613, 5.4113) (-16.1285, 5.3769) (-16.0956, 5.3427) (-16.0626, 5.3088) (-16.0294, 5.2751) (-15.9961, 5.2417) (-15.9626, 5.2086) (-15.9289, 5.1757) (-15.8952, 5.1432) (-15.8612, 5.1108) (-15.8271, 5.0788) (-15.7929, 5.0471) (-15.7585, 5.0156) (-15.724, 4.9844) (-15.6893, 4.9535) (-15.6545, 4.9229) (-15.6195, 4.8927) (-15.5843, 4.8627) (-15.549, 4.833) (-15.5136, 4.8037) (-15.478, 4.7747) (-15.4423, 4.746) (-15.4064, 4.7176) (-15.3703, 4.6895) (-15.3341, 4.6618) (-15.2977, 4.6344) (-15.2612, 4.6074) (-15.2245, 4.5808) (-15.1876, 4.5546) (-15.1506, 4.5288) (-15.1134, 4.5034) (-15.076, 4.4783) (-15.0385, 4.4535) (-15.0009, 4.4291) (-14.9631, 4.4052) (-14.9251, 4.3818) (-14.8868, 4.3589) (-14.8483, 4.3367) (-14.8096, 4.3152) (-14.7707, 4.2941) (-14.7316, 4.2735) (-14.6924, 4.2533) (-14.6531, 4.2333) (-14.6136, 4.2138) (-14.5739, 4.1951) (-14.5338, 4.1777) (-14.5011, 4.1653) (-14.4763, 4.157) (-14.4595, 4.152) (-14.4511, 4.1495) knots -1 -1 -1 -1 -1 -1 -0.98571429 -0.97142857 -0.95714286 -0.94285714 -0.92857143 -0.91428571 -0.9 -0.88571429 -0.87142857 -0.85714286 -0.84285714 -0.82857143 -0.81428571 -0.8 -0.78571429 -0.77142857 -0.75714286 -0.74285714 -0.72857143 -0.71428571 -0.7 -0.68571429 -0.67142857 -0.65714286 -0.64285714 -0.62857143 -0.61428571 -0.6 -0.58571429 -0.57142857 -0.55714286 -0.54285714 -0.52857143 -0.51428571 -0.5 -0.48571429 -0.47142857 -0.45714286 -0.44285714 -0.42857143 -0.41428571 -0.4 -0.38571429 -0.37142857 -0.35714286 -0.34285714 -0.32857143 -0.31428571 -0.3 -0.28571429 -0.27142857 -0.25714286 -0.24285714 -0.22857143 -0.21428571 -0.2 -0.18571429 -0.17142857 -0.15714286 -0.14285714 -0.12857143 -0.11428571 -0.1 -0.08571429 -0.07142857 -0.05714286 -0.04285714 -0.02857143 -0.01428571 0 0 0 0 0 0
  line L31 (-14.4511, 4.1495) -> (-14.0828, 4.0438)
  arc A63 (-13.3811, 2.8727) -> (-14.0828, 4.0438) centre (-14.3588, 3.0826) ccw
  circle A64 centre (0, 0) radius 5
  circle A65 centre (0, 0) radius 5
  dimension "d9" = 10
  constraint concentric A0 A65
  measures "d9" diameter of A65
extrude "Extrude3" add sketch "Sketch4" against normal blind 50 contours A64 A65
named bodies: "Spur Gear (16 teeth)"

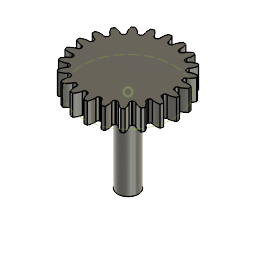
design "planet gear"
description: Spur Gear; Module: 2.0; Num Teeth: 22; Pressure Angle: 20.0; Backlash: 0.00 mm
part number: 2026-09-30-00-16-40-142
Autodesk Fusion 360 part; units mm, degrees
sketch "Base Circle" plane through (0, 0, 0) normal (0, 0, 1) x (1, 0, 0)
  circle A0 centre (0, 0) radius 19.686
  circle A1 centre (0, 0) radius 5
extrude "Extrude1" add sketch "Base Circle" along normal blind 10
sketch "Gear Tooth" plane through (0, 0, 0) normal (0, 0, 1) x (1, 0, 0)
  spline S0 degree 5 poles (20.5963, -1.782) (20.606, -1.7828) (20.6255, -1.7842) (20.6547, -1.7856) (20.6937, -1.7861) (20.7426, -1.7846) (20.7915, -1.7818) (20.8404, -1.7781) (20.8894, -1.7739) (20.9384, -1.7693) (20.9874, -1.7645) (21.0364, -1.7592) (21.0854, -1.7533) (21.1344, -1.7468) (21.1835, -1.7395) (21.2325, -1.7317) (21.2815, -1.7232) (21.3306, -1.7143) (21.3796, -1.705) (21.4286, -1.6954) (21.4776, -1.6853) (21.5266, -1.6749) (21.5756, -1.6641) (21.6246, -1.6528) (21.6736, -1.6411) (21.7225, -1.629) (21.7714, -1.6165) (21.8204, -1.6036) (21.8693, -1.5904) (21.9182, -1.5768) (21.967, -1.5629) (22.0159, -1.5487) (22.0647, -1.5341) (22.1135, -1.5191) (22.1622, -1.5038) (22.211, -1.4882) (22.2597, -1.4723) (22.3084, -1.456) (22.3571, -1.4394) (22.4057, -1.4225) (22.4543, -1.4053) (22.5029, -1.3878) (22.5514, -1.37) (22.6, -1.3519) (22.6484, -1.3335) (22.6969, -1.3148) (22.7453, -1.2958) (22.7937, -1.2765) (22.842, -1.2569) (22.8903, -1.237) (22.9386, -1.2169) (22.9868, -1.1964) (23.035, -1.1757) (23.0832, -1.1548) (23.1313, -1.1335) (23.1794, -1.112) (23.2274, -1.0902) (23.2754, -1.0681) (23.3233, -1.0457) (23.3712, -1.0231) (23.4191, -1.0003) (23.4669, -0.9772) (23.5146, -0.9538) (23.5624, -0.9301) (23.61, -0.9062) (23.6577, -0.8821) (23.7052, -0.8577) (23.7528, -0.833) (23.8002, -0.8081) (23.8477, -0.7829) (23.895, -0.7575) (23.9329, -0.737) (23.9613, -0.7215) (23.9802, -0.7111) (23.9896, -0.7059) knots 0 0 0 0 0 0 0.01428571 0.02857143 0.04285714 0.05714286 0.07142857 0.08571429 0.1 0.11428571 0.12857143 0.14285714 0.15714286 0.17142857 0.18571429 0.2 0.21428571 0.22857143 0.24285714 0.25714286 0.27142857 0.28571429 0.3 0.31428571 0.32857143 0.34285714 0.35714286 0.37142857 0.38571429 0.4 0.41428571 0.42857143 0.44285714 0.45714286 0.47142857 0.48571429 0.5 0.51428571 0.52857143 0.54285714 0.55714286 0.57142857 0.58571429 0.6 0.61428571 0.62857143 0.64285714 0.65714286 0.67142857 0.68571429 0.7 0.71428571 0.72857143 0.74285714 0.75714286 0.77142857 0.78571429 0.8 0.81428571 0.82857143 0.84285714 0.85714286 0.87142857 0.88571429 0.9 0.91428571 0.92857143 0.94285714 0.95714286 0.97142857 0.98571429 1 1 1 1 1 1
  spline S1 degree 5 poles (20.5963, 1.782) (20.606, 1.7828) (20.6255, 1.7842) (20.6547, 1.7856) (20.6937, 1.7861) (20.7426, 1.7846) (20.7915, 1.7818) (20.8404, 1.7781) (20.8894, 1.7739) (20.9384, 1.7693) (20.9874, 1.7645) (21.0364, 1.7592) (21.0854, 1.7533) (21.1344, 1.7468) (21.1835, 1.7395) (21.2325, 1.7317) (21.2815, 1.7232) (21.3306, 1.7143) (21.3796, 1.705) (21.4286, 1.6954) (21.4776, 1.6853) (21.5266, 1.6749) (21.5756, 1.6641) (21.6246, 1.6528) (21.6736, 1.6411) (21.7225, 1.629) (21.7714, 1.6165) (21.8204, 1.6036) (21.8693, 1.5904) (21.9182, 1.5768) (21.967, 1.5629) (22.0159, 1.5487) (22.0647, 1.5341) (22.1135, 1.5191) (22.1622, 1.5038) (22.211, 1.4882) (22.2597, 1.4723) (22.3084, 1.456) (22.3571, 1.4394) (22.4057, 1.4225) (22.4543, 1.4053) (22.5029, 1.3878) (22.5514, 1.37) (22.6, 1.3519) (22.6484, 1.3335) (22.6969, 1.3148) (22.7453, 1.2958) (22.7937, 1.2765) (22.842, 1.2569) (22.8903, 1.237) (22.9386, 1.2169) (22.9868, 1.1964) (23.035, 1.1757) (23.0832, 1.1548) (23.1313, 1.1335) (23.1794, 1.112) (23.2274, 1.0902) (23.2754, 1.0681) (23.3233, 1.0457) (23.3712, 1.0231) (23.4191, 1.0003) (23.4669, 0.9772) (23.5146, 0.9538) (23.5624, 0.9301) (23.61, 0.9062) (23.6577, 0.8821) (23.7052, 0.8577) (23.7528, 0.833) (23.8002, 0.8081) (23.8477, 0.7829) (23.895, 0.7575) (23.9329, 0.737) (23.9613, 0.7215) (23.9802, 0.7111) (23.9896, 0.7059) knots 0 0 0 0 0 0 0.01428571 0.02857143 0.04285714 0.05714286 0.07142857 0.08571429 0.1 0.11428571 0.12857143 0.14285714 0.15714286 0.17142857 0.18571429 0.2 0.21428571 0.22857143 0.24285714 0.25714286 0.27142857 0.28571429 0.3 0.31428571 0.32857143 0.34285714 0.35714286 0.37142857 0.38571429 0.4 0.41428571 0.42857143 0.44285714 0.45714286 0.47142857 0.48571429 0.5 0.51428571 0.52857143 0.54285714 0.55714286 0.57142857 0.58571429 0.6 0.61428571 0.62857143 0.64285714 0.65714286 0.67142857 0.68571429 0.7 0.71428571 0.72857143 0.74285714 0.75714286 0.77142857 0.78571429 0.8 0.81428571 0.82857143 0.84285714 0.85714286 0.87142857 0.88571429 0.9 0.91428571 0.92857143 0.94285714 0.95714286 0.97142857 0.98571429 1 1 1 1 1 1
  arc A0 (23.9896, -0.7059) -> (23.9896, 0.7059) centre (0, 0) ccw
  line L0 (19.6028, -1.696) -> (20.5963, -1.782)
  line L1 (19.6028, 1.696) -> (20.5963, 1.782)
  line L2 (19.6028, -1.696) -> (19.6028, 1.696)
  point P0 (20.8351, -1.7784)
  point P1 (21.0756, -1.7544)
  point P2 (21.3171, -1.7167)
  point P3 (21.5593, -1.6676)
  point P4 (21.8021, -1.6084)
  point P5 (22.0453, -1.5398)
  point P6 (22.2887, -1.4626)
  point P7 (22.5322, -1.377)
  point P8 (22.7757, -1.2836)
  point P9 (23.0191, -1.1825)
  point P10 (23.2623, -1.074)
  point P11 (23.5052, -0.9583)
  point P12 (23.7477, -0.8356)
  point P13 (20.8351, 1.7784)
  point P14 (21.0756, 1.7544)
  point P15 (21.3171, 1.7167)
  point P16 (21.5593, 1.6676)
  point P17 (21.8021, 1.6084)
  point P18 (22.0453, 1.5398)
  point P19 (22.2887, 1.4626)
  point P20 (22.5322, 1.377)
  point P21 (22.7757, 1.2836)
  point P22 (23.0191, 1.1825)
  point P23 (23.2623, 1.074)
  point P24 (23.5052, 0.9583)
  point P25 (23.7477, 0.8356)
extrude "Extrude2" add sketch "Gear Tooth" along normal blind 10
fillet "Fillet1" radius 1 2 edges at (19.6127, -1.6969, 5) (19.6127, 1.6969, 5)
pattern_circular "C-Pattern1" count 22 over 360 about axis through (0, 0, 0) along (0, 0, 1) of "Extrude2", "Fillet1"
sketch "Diametrial Pitch Circle" plane through (0, 0, 0) normal (0, 0, 1) x (1, 0, 0)
  circle A0 centre (0, 0) radius 22 construction